Autodesk Fusion 360 part; units mm, degrees
(part 2 of 2)
sketch "Sketch1 (5)" plane through (0, 0, 0) normal (0, 1, 0) x (1, 0, 0) in component "USB C Hub"
  line L0 (-106, 25) -> (-146, 25) construction
  line L1 (-146, 55) -> (-106, 55) construction
  line L2 (-146, 25) -> (-146, 55) construction
  arc A0 (-106, 41.5) -> (-106, 38.5) centre (-106, 40) ccw construction
  arc A1 (-146, 38.5) -> (-146, 41.5) centre (-146, 40) ccw construction
  line L3 (-146, 40) -> (-106, 40) construction
  line L4 (-106, 55) -> (-106, 25) construction
  line L5 (-126, 55) -> (-126, 25) construction
  line L6 (-150, 35) -> (-102, 35)
  line L7 (-102, 35) -> (-102, 55)
  line L8 (-102, 55) -> (-150, 55)
  line L9 (-150, 55) -> (-150, 35)
  line L10 (-146, 40) -> (-144.6, 40) construction
  circle A2 centre (-144.6, 40) radius 2.25
  circle A3 centre (-107.4, 40) radius 2.25
  dimension "d240" = 40
  dimension "d241" = 30
  dimension "d242" = 3
  dimension "d302" = 4
  dimension "d312" = 1.4
  dimension "d313" = 4.5
  constraint horizontal L1
  constraint vertical L4
  constraint horizontal L0
  constraint vertical L2
  constraint midpoint L5.start L1
  constraint midpoint L5.end L0
  constraint midpoint A1.centre L2
  constraint midpoint A0.centre L4
  constraint coincident A1.centre L3.start
  constraint coincident A1.end L2
  constraint coincident A1.start L2
  constraint symmetric A0.start A1.end L5
  constraint symmetric A0.end A1.start L5
  constraint symmetric A0 A1 L5
  constraint horizontal L6
  constraint vertical L7
  constraint horizontal L8
  constraint vertical L9
  constraint parallel L3 L10
  constraint coincident L10.end A2.centre
  constraint symmetric L5 A2 A3
  measures "d240" distance of L1.end L1.start
  measures "d241" distance of L0.end L1.start
  measures "d242" diameter of A1
  measures "d302" distance of A1.centre L9
  measures "d312" distance of A1.centre L10.end
  measures "d313" diameter of A2
extrude "Extrude1''''" add sketch "Sketch1 (5)" against normal blind 3 separate body makes body 6 in component "USB C Hub"
sketch "Sketch2 (2)" plane through (0, 0, -55) normal (0, 0, -1) x (-1, 0, 0) in component "USB C Hub"
  line L0 (150, 0) -> (102, 0)
  line L1 (102, 0) -> (102, -3)
  line L2 (102, -3) -> (150, -3)
  line L3 (150, -3) -> (150, 0)
  line L4 (150, 0) -> (102, 0)
  line L5 (102, 0) -> (102, -6)
  line L6 (102, -6) -> (150, -6)
  line L7 (150, -6) -> (150, 0)
  line L8 (150, -3) -> (102, -3) construction
  line L9 (126, -6) -> (126, 0) construction
  circle A0 centre (126, -3) radius 2.25
  circle A1 centre (145, -3) radius 2.25
  circle A2 centre (107, -3) radius 2.25
  dimension "d289" = 6
  dimension "d290" = 4.5
  dimension "d291" = 4.5
  constraint horizontal L4
  constraint vertical L5
  constraint horizontal L6
  constraint vertical L7
  constraint coincident L0.start L3.end
  constraint coincident L2.end L3.start
  constraint coincident L1.end L2.start
  constraint midpoint L6 L9.start
  constraint midpoint L4 L9.end
  constraint midpoint L9 A0.centre
  constraint coincident L8 A1.centre
  constraint symmetric L9 A1 A2
  measures "d289" distance of L0.start L6.end
  measures "d290" diameter of A0
  measures "d291" diameter of A1
extrude "Extrude2''" add sketch "Sketch2 (2)" against normal blind 3 contours L0 L1 L2 L3 L4 L5 L7 A0 A1 A2 | L2 L5 L6 L7 A0 A1 A2 bodies 6 in component "USB C Hub"
extrude "Extrude3'" cut sketch "Sketch2 (2)" against normal blind 5 contours L2 A1 | L2 A2 | L2 A0 picked at (144.2749, -2.6672) picked at (107.6157, -2.0527) picked at (126.5498, -2.2663) bodies 6 in component "USB C Hub"
component "Screen Bracket " placed x (1, 0, 0) y (0, 1, 0) z (0, 0, 1) at (0, 0, 0)
component "screen numb retention thingys" placed x (1, 0, 0) y (0, 1, 0) z (0, 0, 1) at (0, 0, 0)
component "USB A hub" placed x (1, 0, 0) y (0, 1, 0) z (0, 0, 1) at (0, 0, 0)
component "USB C Hub" placed x (1, 0, 0) y (0, 1, 0) z (0, 0, 1) at (0, 0, 0)
component "Base" placed x (1, 0, 0) y (0, 1, 0) z (0, 0, 1) at (0, 0, 0)
equation "d1 = 7.25 in + 2 mm"
equation "d10 = ( 25 / 2 ) * 1 mm"
equation "d30 = 4.30 mm + 0.5 mm"
equation "d33 = 4.30 mm + 0.5 mm"
equation "d90 = ( 17 / 2 ) * 1 mm"
equation "d214 = 78 mm + 9.1 mm"
equation "d274 = 6 mm + 3 mm"
equation "d303 = 4 mm + 1.5 mm"
equation "d312 = ( 2.8 / 2 ) * 1 mm"
